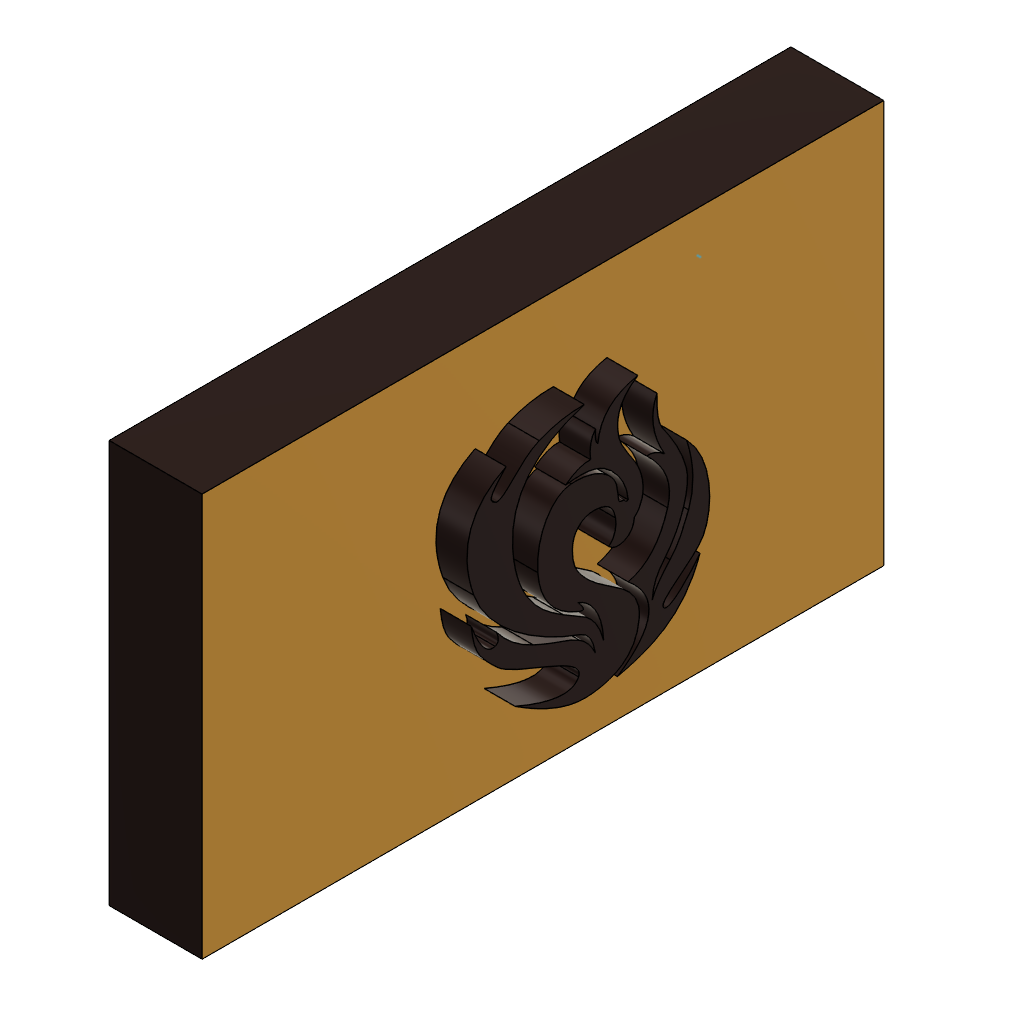
phoenix_robot_chassis (Autodesk Fusion 360 archive; units mm, degrees)
design "emblem"
part number: 2026-10-29-10-37-37-933
Autodesk Fusion 360 part; units mm, degrees
sketch "Sketch1" plane through (0, 0, 0) normal (0, 1, 0) x (1, 0, 0)
  line L0 (0, 30) -> (0.22, 30)
  line L1 (0.22, 30) -> (0.22, 29.97)
  line L2 (0.22, 29.97) -> (0, 29.97)
  line L3 (0, 29.97) -> (0, 30)
  dimension "d1" = 0.22
  dimension "d2" = 0.03
  constraint horizontal L0
  constraint vertical L1
  constraint horizontal L2
  constraint vertical L3
  measures "d1" distance of L0.start L0.end
  measures "d2" distance of L0.start L2.end
sketch "Sketch2" plane through (0, 0, 0) normal (0, 1, 0) x (1, 0, 0)
  line L0 (0, -5) -> (3, -5)
  line L1 (3, -5) -> (3, -27)
  line L2 (3, -27) -> (0, -27)
  line L3 (0, -27) -> (0, -5)
  dimension "d3" = 3
  dimension "d4" = 22
  constraint horizontal L0
  constraint vertical L1
  constraint horizontal L2
  constraint vertical L3
  measures "d3" distance of L0.start L0.end
  measures "d4" distance of L0.start L2.end
extrude "Extrude1" add sketch "Sketch2" along normal blind 13
sketch "Sketch3" plane through (3, 0, 0) normal (1, 0, 0) x (0, 0, -1)
  line L0 (-27, 0) -> (-5, 0)
  line L1 (-5, 0) -> (-5, 13)
  line L2 (-5, 13) -> (-27, 13)
  line L3 (-27, 13) -> (-27, 0)
  spline S0 degree 2 poles (-15.6645, 10.3359) (-16.4385, 10.3449) (-17.1228, 10.0559) knots 0 0 0 1 1 1
  spline S1 degree 3 poles (-17.1228, 10.0559) (-17.7844, 9.7766) (-18.2482, 8.9104) (-18.5369, 9.0395) knots 0 0 0 0 1 1 1 1
  spline S2 degree 3 poles (-18.5369, 9.0395) (-18.8168, 9.1647) (-18.6326, 9.3784) (-18.1907, 9.8645) knots 0 0 0 0 1 1 1 1
  spline S3 degree 3 poles (-18.1907, 9.8645) (-19.2808, 9.3195) (-19.77, 8.3604) (-19.2353, 6.7956) knots 0 0 0 0 1 1 1 1
  spline S4 degree 3 poles (-19.2353, 6.7956) (-18.8178, 5.5736) (-17.2948, 4.5021) (-15.7973, 3.9717) knots 0 0 0 0 1 1 1 1
  spline S5 degree 2 poles (-15.7973, 3.9717) (-15.4072, 3.8335) (-15.311, 3.2211) knots 0 0 0 1 1 1
  spline S6 degree 2 poles (-15.311, 3.2211) (-15.5149, 3.6358) (-15.8224, 3.8269) knots 0 0 0 1 1 1
  spline S7 degree 3 poles (-15.8224, 3.8269) (-16.1982, 4.0604) (-16.4841, 4.0615) (-17.3143, 4.4437) knots 0 0 0 0 1 1 1 1
  spline S8 degree 2 poles (-17.3143, 4.4437) (-18.04, 4.7778) (-18.498, 5.3856) knots 0 0 0 1 1 1
  spline S9 degree 2 poles (-18.498, 5.3856) (-18.368, 5.0771) (-18.5447, 5.0182) knots 0 0 0 1 1 1
  spline S10 degree 3 poles (-18.5447, 5.0182) (-18.7215, 4.9593) (-19.0032, 5.0802) (-19.3133, 5.9609) knots 0 0 0 0 1 1 1 1
  spline S11 degree 3 poles (-19.3133, 5.9609) (-19.2275, 5.0443) (-18.9535, 4.8644) (-18.4929, 4.4143) knots 0 0 0 0 1 1 1 1
  spline S12 degree 3 poles (-18.4929, 4.4143) (-17.9088, 3.8435) (-15.6055, 3.3664) (-15.8524, 2.8199) knots 0 0 0 0 1 1 1 1
  spline S13 degree 2 poles (-15.8524, 2.8199) (-16.1104, 2.249) (-17.9001, 3.0192) knots 0 0 0 1 1 1
  spline S14 degree 3 poles (-17.9001, 3.0192) (-16.3484, 2.0151) (-15.6865, 2.0858) (-15.2387, 2.1587) knots 0 0 0 0 1 1 1 1
  spline S15 degree 3 poles (-15.2387, 2.1587) (-14.7908, 2.2317) (-13.9886, 2.4556) (-13.8949, 3.4763) knots 0 0 0 0 1 1 1 1
  spline S16 degree 3 poles (-13.8949, 3.4763) (-13.8011, 4.4971) (-14.9019, 4.7471) (-15.5302, 5.3668) knots 0 0 0 0 1 1 1 1
  spline S17 degree 3 poles (-15.5302, 5.3668) (-16.0259, 5.8557) (-16.0422, 6.089) (-16.0514, 6.4648) knots 0 0 0 0 1 1 1 1
  spline S18 degree 3 poles (-16.0514, 6.4648) (-16.0619, 6.891) (-15.7693, 7.2377) (-15.3405, 7.2204) knots 0 0 0 0 1 1 1 1
  spline S19 degree 3 poles (-15.3405, 7.2204) (-14.7657, 7.1973) (-14.7012, 6.8611) (-14.6603, 6.6648) knots 0 0 0 0 1 1 1 1
  spline S20 degree 3 poles (-14.6603, 6.6648) (-14.6169, 6.4564) (-14.6636, 6.128) (-14.8799, 5.9799) knots 0 0 0 0 1 1 1 1
  spline S21 degree 3 poles (-14.8799, 5.9799) (-14.7416, 5.8283) (-14.5546, 5.8129) (-14.3696, 5.8891) knots 0 0 0 0 1 1 1 1
  spline S22 degree 3 poles (-14.3696, 5.8891) (-14.1584, 5.976) (-14.0663, 6.1671) (-14.0516, 6.3807) knots 0 0 0 0 1 1 1 1
  spline S23 degree 3 poles (-14.0516, 6.3807) (-13.8452, 6.5358) (-13.6658, 6.925) (-13.8368, 7.496) knots 0 0 0 0 1 1 1 1
  spline S24 degree 3 poles (-13.8368, 7.496) (-14.0206, 8.1101) (-14.5303, 8.4272) (-14.5818, 9.047) knots 0 0 0 0 1 1 1 1
  spline S25 degree 3 poles (-14.5818, 9.047) (-14.6001, 9.266) (-14.6608, 9.8281) (-13.939, 10.2848) knots 0 0 0 0 1 1 1 1
  spline S26 degree 2 poles (-13.939, 10.2848) (-15.1274, 10.0545) (-15.2301, 9.0249) knots 0 0 0 1 1 1
  spline S27 degree 2 poles (-15.2301, 9.0249) (-15.3405, 9.1207) (-15.3037, 9.4742) knots 0 0 0 1 1 1
  spline S28 degree 2 poles (-15.3037, 9.4742) (-15.532, 9.2091) (-15.4657, 8.6934) knots 0 0 0 1 1 1
  spline S29 degree 2 poles (-15.4657, 8.6934) (-15.8271, 8.7261) (-16.2697, 8.3876) knots 0 0 0 1 1 1
  spline S30 degree 3 poles (-16.2697, 8.3876) (-15.4469, 8.5074) (-15.0639, 8.308) (-14.7959, 8.049) knots 0 0 0 0 1 1 1 1
  spline S31 degree 2 poles (-14.7959, 8.049) (-14.3012, 7.5707) (-14.249, 6.9606) knots 0 0 0 1 1 1
  spline S32 degree 2 poles (-14.249, 6.9606) (-14.3168, 6.9423) (-14.3532, 6.9918) knots 0 0 0 1 1 1
  spline S33 degree 3 poles (-14.3532, 6.9918) (-14.3949, 7.0751) (-14.4913, 7.0022) (-14.5433, 7.0803) knots 0 0 0 0 1 1 1 1
  spline S34 degree 3 poles (-14.5433, 7.0803) (-14.585, 7.1376) (-14.5657, 7.3715) (-14.6282, 7.5796) knots 0 0 0 0 1 1 1 1
  spline S35 degree 3 poles (-14.6282, 7.5796) (-14.6536, 7.6643) (-14.7314, 7.8294) (-14.896, 7.9748) knots 0 0 0 0 1 1 1 1
  spline S36 degree 3 poles (-14.896, 7.9748) (-15.129, 8.1804) (-15.4877, 8.362) (-16.0916, 8.3325) knots 0 0 0 0 1 1 1 1
  spline S37 degree 3 poles (-16.0916, 8.3325) (-16.6956, 8.303) (-17.2481, 7.434) (-17.1671, 6.3881) knots 0 0 0 0 1 1 1 1
  spline S38 degree 2 poles (-17.1671, 6.3881) (-17.0714, 5.153) (-15.9111, 4.6707) knots 0 0 0 1 1 1
  spline S39 degree 2 poles (-15.9111, 4.6707) (-15.5095, 4.4819) (-15.8647, 4.8968) knots 0 0 0 1 1 1
  spline S40 degree 3 poles (-15.8647, 4.8968) (-15.5146, 4.7851) (-15.0753, 4.3111) (-15.0458, 3.4421) knots 0 0 0 0 1 1 1 1
  spline S41 degree 3 poles (-15.0458, 3.4421) (-15.3109, 4.429) (-15.8704, 4.4756) (-16.341, 4.7971) knots 0 0 0 0 1 1 1 1
  spline S42 degree 3 poles (-16.341, 4.7971) (-16.7284, 5.0617) (-17.8689, 5.6301) (-17.9773, 7.4834) knots 0 0 0 0 1 1 1 1
  spline S43 degree 2 poles (-17.9773, 7.4834) (-18.1014, 9.6065) (-15.6645, 10.3359) knots 0 0 0 1 1 1
  spline S44 degree 2 poles (-13.3219, 9.4811) (-13.6813, 8.7155) (-13.0772, 7.6635) knots 0 0 0 1 1 1
  spline S45 degree 2 poles (-13.0772, 7.6635) (-13.3897, 7.9239) (-13.6553, 7.8927) knots 0 0 0 1 1 1
  spline S46 degree 2 poles (-13.6553, 7.8927) (-12.7123, 7.0037) (-12.9782, 6.1064) knots 0 0 0 1 1 1
  spline S47 degree 2 poles (-12.9782, 6.1064) (-13.3409, 4.882) (-14.2542, 4.6741) knots 0 0 0 1 1 1
  spline S48 degree 2 poles (-14.2542, 4.6741) (-12.7543, 3.4242) (-14.598, 2.2003) knots 0 0 0 1 1 1
  spline S49 degree 3 poles (-14.598, 2.2003) (-13.6033, 2.4295) (-12.4523, 2.8044) (-11.9365, 4.3147) knots 0 0 0 0 1 1 1 1
  spline S50 degree 3 poles (-11.9365, 4.3147) (-12.2282, 3.9085) (-12.9234, 3.1678) (-13.1031, 3.3774) knots 0 0 0 0 1 1 1 1
  spline S51 degree 3 poles (-13.1031, 3.3774) (-13.3121, 3.6212) (-12.1045, 4.2324) (-11.8272, 4.76) knots 0 0 0 0 1 1 1 1
  spline S52 degree 3 poles (-11.8272, 4.76) (-11.485, 5.4112) (-11.5147, 6.8303) (-12.3636, 7.6895) knots 0 0 0 0 1 1 1 1
  spline S53 degree 3 poles (-12.3636, 7.6895) (-12.1084, 6.8823) (-12.1083, 6.2243) (-12.301, 5.7104) knots 0 0 0 0 1 1 1 1
  spline S54 degree 3 poles (-12.301, 5.7104) (-12.4555, 5.2986) (-12.6406, 4.8914) (-12.9, 4.6167) knots 0 0 0 0 1 1 1 1
  spline S55 degree 3 poles (-12.9, 4.6167) (-13.1881, 4.3115) (-13.4208, 3.9762) (-13.4729, 3.7783) knots 0 0 0 0 1 1 1 1
  spline S56 degree 3 poles (-13.4729, 3.7783) (-13.4521, 4.1949) (-13.3139, 4.4499) (-13.0718, 4.7417) knots 0 0 0 0 1 1 1 1
  spline S57 degree 3 poles (-13.0718, 4.7417) (-12.522, 5.4045) (-12.2272, 6.3834) (-12.374, 6.9239) knots 0 0 0 0 1 1 1 1
  spline S58 degree 3 poles (-12.374, 6.9239) (-12.5198, 7.4655) (-12.7886, 7.9097) (-13.1603, 8.4445) knots 0 0 0 0 1 1 1 1
  spline S59 degree 2 poles (-13.1603, 8.4445) (-13.3449, 8.7101) (-13.3219, 9.4811) knots 0 0 0 1 1 1
extrude "Extrude2" add sketch "Sketch3" along normal blind 1 contours S0 S1 S2 S3 S4 S5 S6 S7 S8 S9 S10 S11 S12 S13 S14 S15 S16 S17 S18 S19 S20 S21 S22 S23 S24 S25 S26 S27 S28 S29 S30 S31 S32 S33 S34 S35 S36 S37 S38 S39 S40 S41 S42 S43 | S44 S45 S46 S47 S48 S49 S50 S51 S52 S53 S54 S55 S56 S57 S58 S59
scale "Scale1" factor 3 about (0, 13, 27) bodies 1
